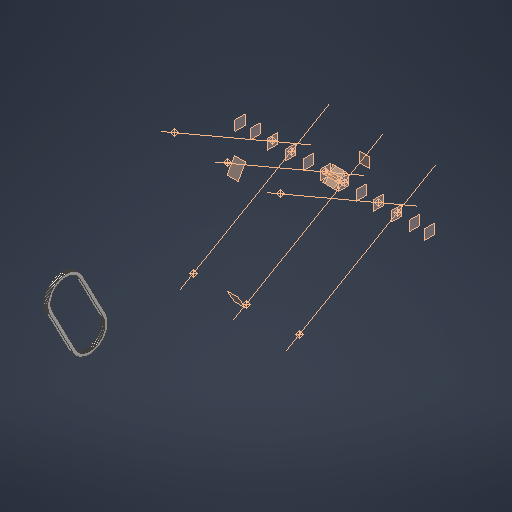
# Autodesk Inventor part: Timing_Chain_Secondary_B_SIMPLIFIED
Saved by Autodesk Inventor 2027.1 (Build 311270010, 270A)
## iProperties
Created: 2026-10-17
Part Number: Timing_Chain_Secondary_B_SIMPLIFIED
Material: Steel, Carbon
Document SubType Name: Modeling
Designer: kashyap
Density: 7.85 g/cm^3
Appearance: Semi-Polished
Material_Status: Assumed for this reconstruction
Author: kashyap
Autodesk Inventor part; units mm, degrees
ref_plane "YZ Plane" through (0, 0, 0) normal (1, 0, 0) x (0, 1, 0)
derived "V6_Engine_Master.ipt"
ref_plane "Bank_A_Plane" through (0, 0, 0) normal (0, 0.8660254, -0.5) x (-1, 0, 0)
ref_plane "Bank_B_Plane" through (0, 0, 0) normal (0, 0.8660254, 0.5) x (-1, 0, 0)
ref_plane "Bank_A_Perp_Plane" through (0, 0, 0) normal (0, 0.5, 0.8660254) x (-1, 0, 0)
ref_plane "Bank_B_Perp_Plane" through (0, 0, 0) normal (0, -0.5, 0.8660254) x (-1, 0, 0)
ref_plane "Bank_A_Deck_Plane" through (0, 112.9, 195.5485) normal (0, 0.5, 0.8660254) x (-1, 0, 0)
ref_plane "Bank_B_Deck_Plane" through (0, -112.9, 195.5485) normal (0, -0.5, 0.8660254) x (-1, 0, 0)
ref_plane "Cyl_A1_Station_Plane" through (-123.8, 0, 0) normal (1, 0, 0) x (0, 1, 0)
ref_plane "Cyl_A2_Station_Plane" through (-18.3, 0, 0) normal (1, 0, 0) x (0, 1, 0)
ref_plane "Cyl_A3_Station_Plane" through (87.2, 0, 0) normal (1, 0, 0) x (0, 1, 0)
ref_plane "Cyl_B1_Station_Plane" through (-87.2, 0, 0) normal (1, 0, 0) x (0, 1, 0)
ref_plane "Cyl_B2_Station_Plane" through (18.3, 0, 0) normal (1, 0, 0) x (0, 1, 0)
ref_plane "Cyl_B3_Station_Plane" through (123.8, 0, 0) normal (1, 0, 0) x (0, 1, 0)
ref_plane "Main_Bearing_Station_1" through (-158.25, 0, 0) normal (1, 0, 0) x (0, 1, 0)
ref_plane "Main_Bearing_Station_2" through (-52.75, 0, 0) normal (1, 0, 0) x (0, 1, 0)
ref_plane "Main_Bearing_Station_3" through (52.75, 0, 0) normal (1, 0, 0) x (0, 1, 0)
ref_plane "Main_Bearing_Station_4" through (158.25, 0, 0) normal (1, 0, 0) x (0, 1, 0)
ref_plane "Front_Interface" through (-188.25, 0, 0) normal (1, 0, 0) x (0, 1, 0)
ref_plane "Rear_Interface" through (188.25, 0, 0) normal (1, 0, 0) x (0, 1, 0)
ref_plane "Oil_Pan_Plane" through (0, 0, -60) normal (0, 0, 1) x (1, 0, 0)
ref_plane "Primary_Sprocket_Plane" through (-193.75, 0, 0) normal (1, 0, 0) x (0, 1, 0)
ref_plane "Secondary_Sprocket_Plane" through (-203.75, 0, 0) normal (1, 0, 0) x (0, 1, 0)
sketch "SK_Chain" plane through (-203.75, 0, 0) normal (1, 0, 0) x (0, 1, 0)
  line L0 (-261.5577, 288.2542) -> (-261.5071, 286.3216)
  line L1 (-261.5071, 286.3216) -> (-261.3554, 284.3944)
  line L2 (-261.3554, 284.3944) -> (-261.1031, 282.4777)
  line L3 (-261.1031, 282.4777) -> (-260.7508, 280.5768)
  line L4 (-260.7508, 280.5768) -> (-260.2995, 278.697)
  line L5 (-260.2995, 278.697) -> (-259.7504, 276.8434)
  line L6 (-259.7504, 276.8434) -> (-259.1051, 275.0211)
  line L7 (-259.1051, 275.0211) -> (-258.3653, 273.235)
  line L8 (-258.3653, 273.235) -> (-257.533, 271.4901)
  line L9 (-257.533, 271.4901) -> (-256.6106, 269.7911)
  line L10 (-256.6106, 269.7911) -> (-255.6005, 268.1428)
  line L11 (-255.6005, 268.1428) -> (-254.5055, 266.5496)
  line L12 (-254.5055, 266.5496) -> (-253.3286, 265.0158)
  line L13 (-253.3286, 265.0158) -> (-252.0731, 263.5458)
  line L14 (-252.0731, 263.5458) -> (-250.7423, 262.1435)
  line L15 (-250.7423, 262.1435) -> (-249.34, 260.8127)
  line L16 (-249.34, 260.8127) -> (-247.87, 259.5572)
  line L17 (-247.87, 259.5572) -> (-246.3362, 258.3803)
  line L18 (-246.3362, 258.3803) -> (-244.743, 257.2853)
  line L19 (-244.743, 257.2853) -> (-243.0947, 256.2752)
  line L20 (-243.0947, 256.2752) -> (-241.3957, 255.3528)
  line L21 (-241.3957, 255.3528) -> (-239.6508, 254.5205)
  line L22 (-239.6508, 254.5205) -> (-237.8647, 253.7807)
  line L23 (-237.8647, 253.7807) -> (-236.0424, 253.1354)
  line L24 (-236.0424, 253.1354) -> (-234.1888, 252.5863)
  line L25 (-234.1888, 252.5863) -> (-232.309, 252.135)
  line L26 (-232.309, 252.135) -> (-230.4081, 251.7827)
  line L27 (-230.4081, 251.7827) -> (-228.4914, 251.5303)
  line L28 (-228.4914, 251.5303) -> (-226.5641, 251.3787)
  line L29 (-226.5641, 251.3787) -> (-224.6316, 251.3281)
  line L30 (-224.6316, 251.3281) -> (-222.699, 251.3787)
  line L31 (-222.699, 251.3787) -> (-220.7717, 251.5303)
  line L32 (-220.7717, 251.5303) -> (-218.8551, 251.7827)
  line L33 (-218.8551, 251.7827) -> (-216.9542, 252.135)
  line L34 (-216.9542, 252.135) -> (-215.0744, 252.5863)
  line L35 (-215.0744, 252.5863) -> (-213.2208, 253.1354)
  line L36 (-213.2208, 253.1354) -> (-211.3984, 253.7807)
  line L37 (-211.3984, 253.7807) -> (-209.6124, 254.5205)
  line L38 (-209.6124, 254.5205) -> (-207.8675, 255.3528)
  line L39 (-207.8675, 255.3528) -> (-119.3015, 301.3885)
  line L40 (-119.3015, 301.3885) -> (-117.6026, 302.311)
  line L41 (-117.6026, 302.311) -> (-115.9542, 303.3211)
  line L42 (-115.9542, 303.3211) -> (-114.361, 304.4161)
  line L43 (-114.361, 304.4161) -> (-112.8273, 305.593)
  line L44 (-112.8273, 305.593) -> (-111.3572, 306.8485)
  line L45 (-111.3572, 306.8485) -> (-109.9549, 308.1792)
  line L46 (-109.9549, 308.1792) -> (-108.6242, 309.5816)
  line L47 (-108.6242, 309.5816) -> (-107.3687, 311.0516)
  line L48 (-107.3687, 311.0516) -> (-106.1918, 312.5853)
  line L49 (-106.1918, 312.5853) -> (-105.0968, 314.1785)
  line L50 (-105.0968, 314.1785) -> (-104.0867, 315.8269)
  line L51 (-104.0867, 315.8269) -> (-103.1642, 317.5258)
  line L52 (-103.1642, 317.5258) -> (-102.3319, 319.2708)
  line L53 (-102.3319, 319.2708) -> (-101.5921, 321.0568)
  line L54 (-101.5921, 321.0568) -> (-100.9468, 322.8792)
  line L55 (-100.9468, 322.8792) -> (-100.3977, 324.7328)
  line L56 (-100.3977, 324.7328) -> (-99.9464, 326.6126)
  line L57 (-99.9464, 326.6126) -> (-99.5941, 328.5134)
  line L58 (-99.5941, 328.5134) -> (-99.3418, 330.4301)
  line L59 (-99.3418, 330.4301) -> (-99.1901, 332.3574)
  line L60 (-99.1901, 332.3574) -> (-99.1395, 334.29)
  line L61 (-99.1395, 334.29) -> (-99.1901, 336.2225)
  line L62 (-99.1901, 336.2225) -> (-99.3418, 338.1498)
  line L63 (-99.3418, 338.1498) -> (-99.5941, 340.0665)
  line L64 (-99.5941, 340.0665) -> (-99.9464, 341.9673)
  line L65 (-99.9464, 341.9673) -> (-100.3977, 343.8472)
  line L66 (-100.3977, 343.8472) -> (-100.9468, 345.7008)
  line L67 (-100.9468, 345.7008) -> (-101.5921, 347.5231)
  line L68 (-101.5921, 347.5231) -> (-102.3319, 349.3092)
  line L69 (-102.3319, 349.3092) -> (-103.1642, 351.0541)
  line L70 (-103.1642, 351.0541) -> (-104.0867, 352.753)
  line L71 (-104.0867, 352.753) -> (-105.0968, 354.4014)
  line L72 (-105.0968, 354.4014) -> (-106.1918, 355.9946)
  line L73 (-106.1918, 355.9946) -> (-107.3687, 357.5283)
  line L74 (-107.3687, 357.5283) -> (-108.6242, 358.9984)
  line L75 (-108.6242, 358.9984) -> (-109.9549, 360.4007)
  line L76 (-109.9549, 360.4007) -> (-111.3572, 361.7314)
  line L77 (-111.3572, 361.7314) -> (-112.8273, 362.987)
  line L78 (-112.8273, 362.987) -> (-114.361, 364.1638)
  line L79 (-114.361, 364.1638) -> (-115.9542, 365.2588)
  line L80 (-115.9542, 365.2588) -> (-117.6026, 366.2689)
  line L81 (-117.6026, 366.2689) -> (-119.3015, 367.1914)
  line L82 (-119.3015, 367.1914) -> (-121.0464, 368.0237)
  line L83 (-121.0464, 368.0237) -> (-122.8325, 368.7635)
  line L84 (-122.8325, 368.7635) -> (-124.6549, 369.4088)
  line L85 (-124.6549, 369.4088) -> (-126.5085, 369.9579)
  line L86 (-126.5085, 369.9579) -> (-128.3883, 370.4092)
  line L87 (-128.3883, 370.4092) -> (-130.2891, 370.7615)
  line L88 (-130.2891, 370.7615) -> (-132.2058, 371.0138)
  line L89 (-132.2058, 371.0138) -> (-134.1331, 371.1655)
  line L90 (-134.1331, 371.1655) -> (-136.0657, 371.2161)
  line L91 (-136.0657, 371.2161) -> (-137.9982, 371.1655)
  line L92 (-137.9982, 371.1655) -> (-139.9255, 371.0138)
  line L93 (-139.9255, 371.0138) -> (-141.8422, 370.7615)
  line L94 (-141.8422, 370.7615) -> (-143.743, 370.4092)
  line L95 (-143.743, 370.4092) -> (-145.6229, 369.9579)
  line L96 (-145.6229, 369.9579) -> (-147.4765, 369.4088)
  line L97 (-147.4765, 369.4088) -> (-149.2988, 368.7635)
  line L98 (-149.2988, 368.7635) -> (-151.0849, 368.0237)
  line L99 (-151.0849, 368.0237) -> (-152.8298, 367.1914)
  line L100 (-152.8298, 367.1914) -> (-241.3957, 321.1556)
  line L101 (-241.3957, 321.1556) -> (-243.0947, 320.2332)
  line L102 (-243.0947, 320.2332) -> (-244.743, 319.2231)
  line L103 (-244.743, 319.2231) -> (-246.3362, 318.1281)
  line L104 (-246.3362, 318.1281) -> (-247.87, 316.9512)
  line L105 (-247.87, 316.9512) -> (-249.34, 315.6957)
  line L106 (-249.34, 315.6957) -> (-250.7423, 314.3649)
  line L107 (-250.7423, 314.3649) -> (-252.0731, 312.9626)
  line L108 (-252.0731, 312.9626) -> (-253.3286, 311.4926)
  line L109 (-253.3286, 311.4926) -> (-254.5055, 309.9589)
  line L110 (-254.5055, 309.9589) -> (-255.6005, 308.3656)
  line L111 (-255.6005, 308.3656) -> (-256.6106, 306.7173)
  line L112 (-256.6106, 306.7173) -> (-257.533, 305.0183)
  line L113 (-257.533, 305.0183) -> (-258.3653, 303.2734)
  line L114 (-258.3653, 303.2734) -> (-259.1051, 301.4874)
  line L115 (-259.1051, 301.4874) -> (-259.7504, 299.665)
  line L116 (-259.7504, 299.665) -> (-260.2995, 297.8114)
  line L117 (-260.2995, 297.8114) -> (-260.7508, 295.9316)
  line L118 (-260.7508, 295.9316) -> (-261.1031, 294.0307)
  line L119 (-261.1031, 294.0307) -> (-261.3554, 292.114)
  line L120 (-261.3554, 292.114) -> (-261.5071, 290.1868)
  line L121 (-261.5071, 290.1868) -> (-261.5577, 288.2542)
  line L122 (-255.5577, 288.2542) -> (-255.5153, 286.6357)
  line L123 (-255.5153, 286.6357) -> (-255.3883, 285.0215)
  line L124 (-255.3883, 285.0215) -> (-255.177, 283.4163)
  line L125 (-255.177, 283.4163) -> (-254.8819, 281.8243)
  line L126 (-254.8819, 281.8243) -> (-254.5039, 280.2499)
  line L127 (-254.5039, 280.2499) -> (-254.0441, 278.6975)
  line L128 (-254.0441, 278.6975) -> (-253.5036, 277.1713)
  line L129 (-253.5036, 277.1713) -> (-252.884, 275.6754)
  line L130 (-252.884, 275.6754) -> (-252.187, 274.214)
  line L131 (-252.187, 274.214) -> (-251.4144, 272.7911)
  line L132 (-251.4144, 272.7911) -> (-250.5684, 271.4106)
  line L133 (-250.5684, 271.4106) -> (-249.6514, 270.0763)
  line L134 (-249.6514, 270.0763) -> (-248.6657, 268.7918)
  line L135 (-248.6657, 268.7918) -> (-247.6142, 267.5606)
  line L136 (-247.6142, 267.5606) -> (-246.4997, 266.3861)
  line L137 (-246.4997, 266.3861) -> (-245.3252, 265.2716)
  line L138 (-245.3252, 265.2716) -> (-244.094, 264.2201)
  line L139 (-244.094, 264.2201) -> (-242.8095, 263.2344)
  line L140 (-242.8095, 263.2344) -> (-241.4752, 262.3174)
  line L141 (-241.4752, 262.3174) -> (-240.0947, 261.4714)
  line L142 (-240.0947, 261.4714) -> (-238.6718, 260.6988)
  line L143 (-238.6718, 260.6988) -> (-237.2104, 260.0018)
  line L144 (-237.2104, 260.0018) -> (-235.7145, 259.3822)
  line L145 (-235.7145, 259.3822) -> (-234.1883, 258.8417)
  line L146 (-234.1883, 258.8417) -> (-232.6359, 258.3818)
  line L147 (-232.6359, 258.3818) -> (-231.0615, 258.0039)
  line L148 (-231.0615, 258.0039) -> (-229.4695, 257.7088)
  line L149 (-229.4695, 257.7088) -> (-227.8642, 257.4975)
  line L150 (-227.8642, 257.4975) -> (-226.2501, 257.3704)
  line L151 (-226.2501, 257.3704) -> (-224.6316, 257.3281)
  line L152 (-224.6316, 257.3281) -> (-223.013, 257.3704)
  line L153 (-223.013, 257.3704) -> (-221.3989, 257.4975)
  line L154 (-221.3989, 257.4975) -> (-219.7937, 257.7088)
  line L155 (-219.7937, 257.7088) -> (-218.2017, 258.0039)
  line L156 (-218.2017, 258.0039) -> (-216.6273, 258.3818)
  line L157 (-216.6273, 258.3818) -> (-215.0749, 258.8417)
  line L158 (-215.0749, 258.8417) -> (-213.5486, 259.3822)
  line L159 (-213.5486, 259.3822) -> (-212.0528, 260.0018)
  line L160 (-212.0528, 260.0018) -> (-210.5914, 260.6988)
  line L161 (-210.5914, 260.6988) -> (-122.0255, 306.7346)
  line L162 (-122.0255, 306.7346) -> (-120.6026, 307.5071)
  line L163 (-120.6026, 307.5071) -> (-119.2221, 308.3531)
  line L164 (-119.2221, 308.3531) -> (-117.8877, 309.2702)
  line L165 (-117.8877, 309.2702) -> (-116.6032, 310.2558)
  line L166 (-116.6032, 310.2558) -> (-115.372, 311.3074)
  line L167 (-115.372, 311.3074) -> (-114.1976, 312.4219)
  line L168 (-114.1976, 312.4219) -> (-113.0831, 313.5963)
  line L169 (-113.0831, 313.5963) -> (-112.0315, 314.8275)
  line L170 (-112.0315, 314.8275) -> (-111.0459, 316.112)
  line L171 (-111.0459, 316.112) -> (-110.1288, 317.4464)
  line L172 (-110.1288, 317.4464) -> (-109.2828, 318.8269)
  line L173 (-109.2828, 318.8269) -> (-108.5103, 320.2498)
  line L174 (-108.5103, 320.2498) -> (-107.8132, 321.7112)
  line L175 (-107.8132, 321.7112) -> (-107.1936, 323.207)
  line L176 (-107.1936, 323.207) -> (-106.6531, 324.7333)
  line L177 (-106.6531, 324.7333) -> (-106.1933, 326.2857)
  line L178 (-106.1933, 326.2857) -> (-105.8153, 327.8601)
  line L179 (-105.8153, 327.8601) -> (-105.5203, 329.4521)
  line L180 (-105.5203, 329.4521) -> (-105.3089, 331.0573)
  line L181 (-105.3089, 331.0573) -> (-105.1819, 332.6714)
  line L182 (-105.1819, 332.6714) -> (-105.1395, 334.29)
  line L183 (-105.1395, 334.29) -> (-105.1819, 335.9085)
  line L184 (-105.1819, 335.9085) -> (-105.3089, 337.5226)
  line L185 (-105.3089, 337.5226) -> (-105.5203, 339.1279)
  line L186 (-105.5203, 339.1279) -> (-105.8153, 340.7199)
  line L187 (-105.8153, 340.7199) -> (-106.1933, 342.2942)
  line L188 (-106.1933, 342.2942) -> (-106.6531, 343.8467)
  line L189 (-106.6531, 343.8467) -> (-107.1936, 345.3729)
  line L190 (-107.1936, 345.3729) -> (-107.8132, 346.8688)
  line L191 (-107.8132, 346.8688) -> (-108.5103, 348.3301)
  line L192 (-108.5103, 348.3301) -> (-109.2828, 349.753)
  line L193 (-109.2828, 349.753) -> (-110.1288, 351.1336)
  line L194 (-110.1288, 351.1336) -> (-111.0459, 352.4679)
  line L195 (-111.0459, 352.4679) -> (-112.0315, 353.7524)
  line L196 (-112.0315, 353.7524) -> (-113.0831, 354.9836)
  line L197 (-113.0831, 354.9836) -> (-114.1976, 356.1581)
  line L198 (-114.1976, 356.1581) -> (-115.372, 357.2726)
  line L199 (-115.372, 357.2726) -> (-116.6032, 358.3241)
  line L200 (-116.6032, 358.3241) -> (-117.8877, 359.3097)
  line L201 (-117.8877, 359.3097) -> (-119.2221, 360.2268)
  line L202 (-119.2221, 360.2268) -> (-120.6026, 361.0728)
  line L203 (-120.6026, 361.0728) -> (-122.0255, 361.8454)
  line L204 (-122.0255, 361.8454) -> (-123.4869, 362.5424)
  line L205 (-123.4869, 362.5424) -> (-124.9827, 363.162)
  line L206 (-124.9827, 363.162) -> (-126.509, 363.7025)
  line L207 (-126.509, 363.7025) -> (-128.0614, 364.1623)
  line L208 (-128.0614, 364.1623) -> (-129.6358, 364.5403)
  line L209 (-129.6358, 364.5403) -> (-131.2277, 364.8354)
  line L210 (-131.2277, 364.8354) -> (-132.833, 365.0467)
  line L211 (-132.833, 365.0467) -> (-134.4471, 365.1737)
  line L212 (-134.4471, 365.1737) -> (-136.0657, 365.2161)
  line L213 (-136.0657, 365.2161) -> (-137.6842, 365.1737)
  line L214 (-137.6842, 365.1737) -> (-139.2983, 365.0467)
  line L215 (-139.2983, 365.0467) -> (-140.9036, 364.8354)
  line L216 (-140.9036, 364.8354) -> (-142.4956, 364.5403)
  line L217 (-142.4956, 364.5403) -> (-144.0699, 364.1623)
  line L218 (-144.0699, 364.1623) -> (-145.6224, 363.7025)
  line L219 (-145.6224, 363.7025) -> (-147.1486, 363.162)
  line L220 (-147.1486, 363.162) -> (-148.6445, 362.5424)
  line L221 (-148.6445, 362.5424) -> (-150.1058, 361.8454)
  line L222 (-150.1058, 361.8454) -> (-238.6718, 315.8096)
  line L223 (-238.6718, 315.8096) -> (-240.0947, 315.037)
  line L224 (-240.0947, 315.037) -> (-241.4752, 314.1911)
  line L225 (-241.4752, 314.1911) -> (-242.8095, 313.274)
  line L226 (-242.8095, 313.274) -> (-244.094, 312.2883)
  line L227 (-244.094, 312.2883) -> (-245.3252, 311.2368)
  line L228 (-245.3252, 311.2368) -> (-246.4997, 310.1223)
  line L229 (-246.4997, 310.1223) -> (-247.6142, 308.9478)
  line L230 (-247.6142, 308.9478) -> (-248.6657, 307.7167)
  line L231 (-248.6657, 307.7167) -> (-249.6514, 306.4321)
  line L232 (-249.6514, 306.4321) -> (-250.5684, 305.0978)
  line L233 (-250.5684, 305.0978) -> (-251.4144, 303.7173)
  line L234 (-251.4144, 303.7173) -> (-252.187, 302.2944)
  line L235 (-252.187, 302.2944) -> (-252.884, 300.833)
  line L236 (-252.884, 300.833) -> (-253.5036, 299.3371)
  line L237 (-253.5036, 299.3371) -> (-254.0441, 297.8109)
  line L238 (-254.0441, 297.8109) -> (-254.5039, 296.2585)
  line L239 (-254.5039, 296.2585) -> (-254.8819, 294.6841)
  line L240 (-254.8819, 294.6841) -> (-255.177, 293.0921)
  line L241 (-255.177, 293.0921) -> (-255.3883, 291.4869)
  line L242 (-255.3883, 291.4869) -> (-255.5153, 289.8728)
  line L243 (-255.5153, 289.8728) -> (-255.5577, 288.2542)
  constraints: 488 end point
extrude "Chain_Band_SIMPLIFIED" add sketch "SK_Chain" along normal mid plane 8
body "Solid2"
